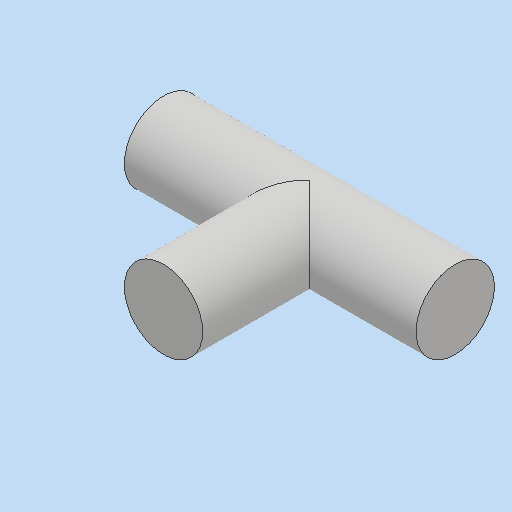
# Autodesk Inventor part: MM0868AN100_G80_540
Saved by Autodesk Inventor 2023.3 (Build 273359000, 359)
## iProperties
RuleStatus: InUse
Created: 2023-01-20
Part Number: MM0868AN100_G80_540
Material: Generisch
Description: =<RBPARTNOTITLE2>
Document SubType Name: Modeling
Designer: fsm9bw
Mass: 47.5277 g
Surface Area: 21.6839 cm^2
Volume: 5.40087 cm^3
Density: 8.8 g/cm^3
Appearance: Vorgabe
Vendor: Fritsche GmbH
AnP_Kategorie: 2
AnP_Material: =<Material>
MaxAbmaße: 8 x 24,5 x 41 (FM)
AnP_TemplVers: 20200821
RBDOCUMENTTYPE: DRF
RBDOCUMENTVERSION: 00
RBDRAWINGMAINSCALE: 1:1
RBDRAWINGMISSINGSPEC: --
RBDRAWINGVOLUME: --
RBDSV1: 0850
RBGBEDGESIN1: +0,5
RBGBEDGESIN2: +0,2
RBGBEDGESOUT1: -0,3
RBGBEDGESOUT2: -0,1
RBGBREMARKSINDEX: E
RBMATERIAL: --
RBMATMEETS: --
RBMATNO: =<Part Number>
RBPARTMADEOF: 2016-101
RBPARTNO: SIEHE MNR
RBPARTNOTITLE1: T plug-in connector
RBPARTNOTITLE2: T-Steckverbinder
RBPARTSAFETYINDICATOR: --
RBSURFACE: --
RBSURFACE2: --
RBZEDGESNORM: ISO13715:2002-06
RBZGENDIMCLASS: m
RBZGENDIMNORM: ISO 2768-1:1989-11
RBZGENGEOCLASS: H
RBZGENGEONORM: ISO 2768-2:1989-11
RBZSURFACENORM: ISO13D2:2002-02
RBZTOLERANCENORM: ISO 14405-1:2010-12
Author: fsm9bw
Keywords: =<RBPARTMADEOF>
Comments: =<RBSURFACE2>
Revision Number: 01
Autodesk Inventor part; units mm, degrees
ref_plane "YZ Plane" through (0, 0, 0) normal (1, 0, 0) x (0, 1, 0)
ref_plane "XZ Plane" through (0, 0, 0) normal (0, 1, 0) x (-1, 0, 0)
ref_plane "XY Plane" through (0, 0, 0) normal (0, 0, 1) x (1, 0, 0)
sketch "Skizze1" plane through (0, 0, 0) normal (0, 0, 1) x (1, 0, 0)
  line L0 (-20.5, -5.5) -> (20.5, -5.5)
  line L1 (20.5, -5.5) -> (20.5, 5.5)
  line L2 (20.5, 5.5) -> (-20.5, 5.5)
  line L3 (-20.5, 5.5) -> (-20.5, -5.5)
  line L4 (-5.5, -20.5) -> (5.5, -20.5)
  line L5 (5.5, -20.5) -> (5.5, 0)
  line L6 (5.5, 0) -> (-5.5, 0)
  line L7 (-5.5, 0) -> (-5.5, -20.5)
  line L8 (-28.7, 0) -> (28.7, 0) projected
  line L9 (0, -25.7) -> (0, 10.7) projected
  point P0 (0, 0)
  point P1 (-5.5, -5.5)
  point P2 (5.5, -5.5)
  dimension "d0" = 41
  dimension "d1" = 20.5
  dimension "d2" = 20.5
  dimension "d3" = 11
  dimension "d4" = 11
  constraints: 16 end point, 4 parallel, 2 horizontal, 2 perpendicular, 1 collinear, 2 other
  measures "d0" distance of L1.end L2.end
  measures "d1" distance between parallel lines of L4 L6
  measures "d2" distance between parallel lines of L9 L3
  measures "d3" distance of L0.end L1.end
  measures "d4" distance of L4.start L4.end
extrude "Extrusion1" add sketch "Skizze1" along normal mid plane 11
fillet "Rundung1" radius 5.5 10 edges at (-5.5, -13, 5.5) (-13, -5.5, 5.5) (-13, -5.5, -5.5) (5.5, -13, 5.5) (13, -5.5, 5.5) (13, -5.5, -5.5) (5.5, -13, -5.5) (0, 5.5, 5.5) (0, 5.5, -5.5) (-5.5, -13, -5.5)
